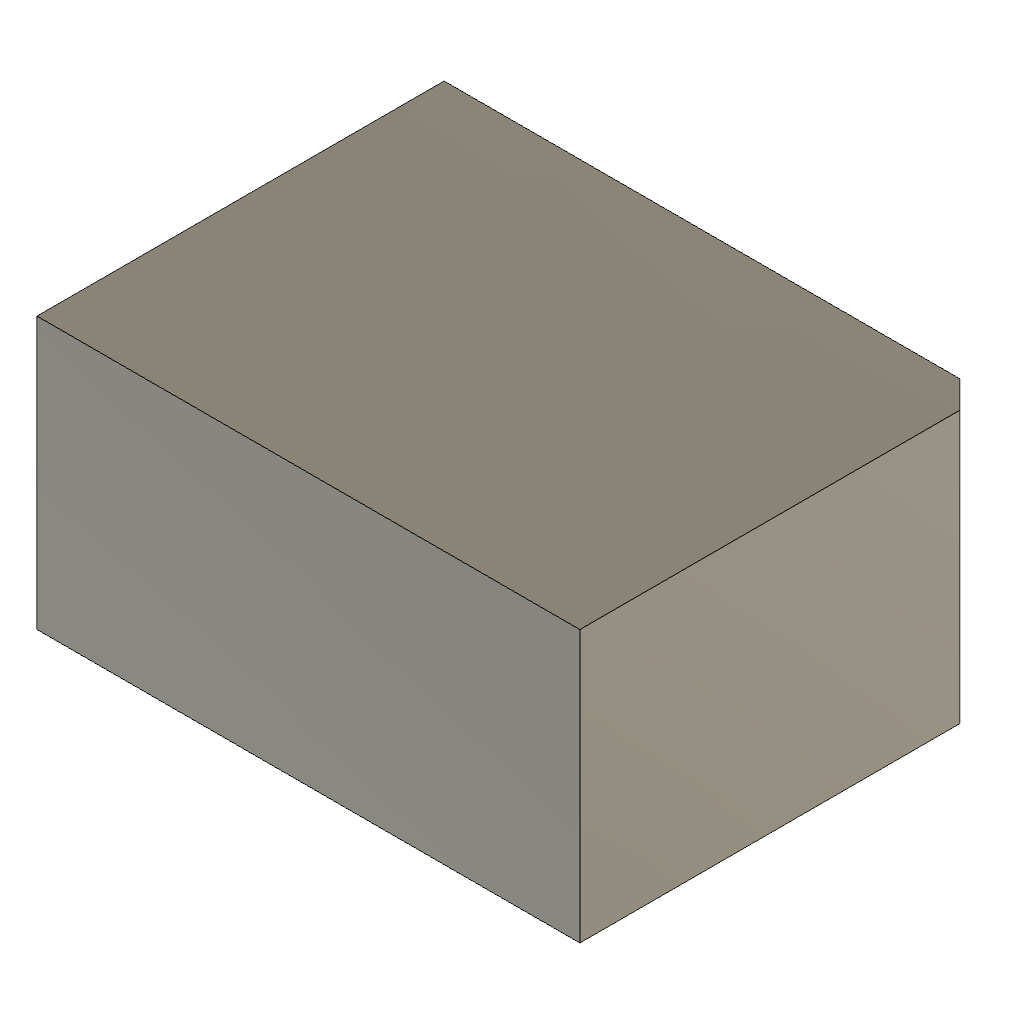
vendor_Chamfer (Autodesk Fusion 360 design; units mm, degrees)
Autodesk Fusion 360 part; units mm, degrees
sketch "Base Sketch" plane through (0, 0, 0) normal (0, 0, 1) x (1, 0, 0)
  line L0 (0, 0) -> (40, 0)
  line L1 (40, 0) -> (40, 30)
  line L2 (40, 30) -> (0, 30)
  line L3 (0, 30) -> (0, 0)
extrude "Base Extrude" add sketch "Base Sketch" along normal blind 20
chamfer "Chamfer" distance 2 angle 45 1 edges at (40, 30, 10) tangent chain off
equation "height = 20.0 mm"
equation "d2 = height"
